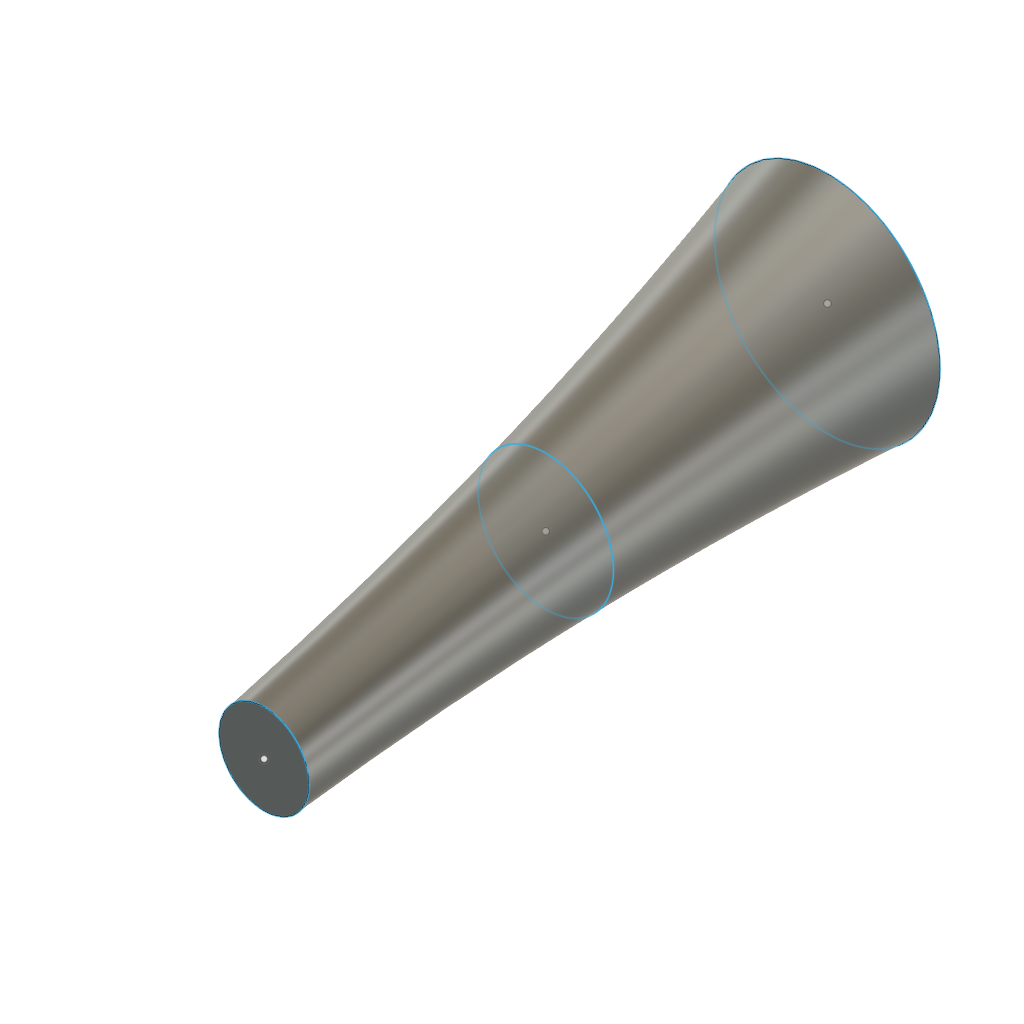
LoftThreeSections (Autodesk Fusion 360 design; units mm, degrees)
part number: 2026-10-20-18-22-11-294
Autodesk Fusion 360 part; units mm, degrees
sketch "LoftSectionOne" plane through (0, 0, 0) normal (0, 0, 1) x (1, 0, 0)
  circle A0 centre (0, 0) radius 10
ref_plane "WorkPlane1" through (0, 0, 30) normal (0, 0, 1) x (1, 0, 0)
sketch "LoftSectionTwo" plane through (0, 0, 30) normal (0, 0, 1) x (1, 0, 0)
  circle A0 centre (5, 0) radius 6
ref_plane "WorkPlane2" through (0, 0, 60) normal (0, 0, 1) x (1, 0, 0)
sketch "LoftSectionThree" plane through (0, 0, 60) normal (0, 0, 1) x (1, 0, 0)
  circle A0 centre (10, 0) radius 4
loft "ProbeLoftThreeSections" add profiles "LoftSectionOne", "LoftSectionTwo", "LoftSectionThree" section 1 section 2 section 3
